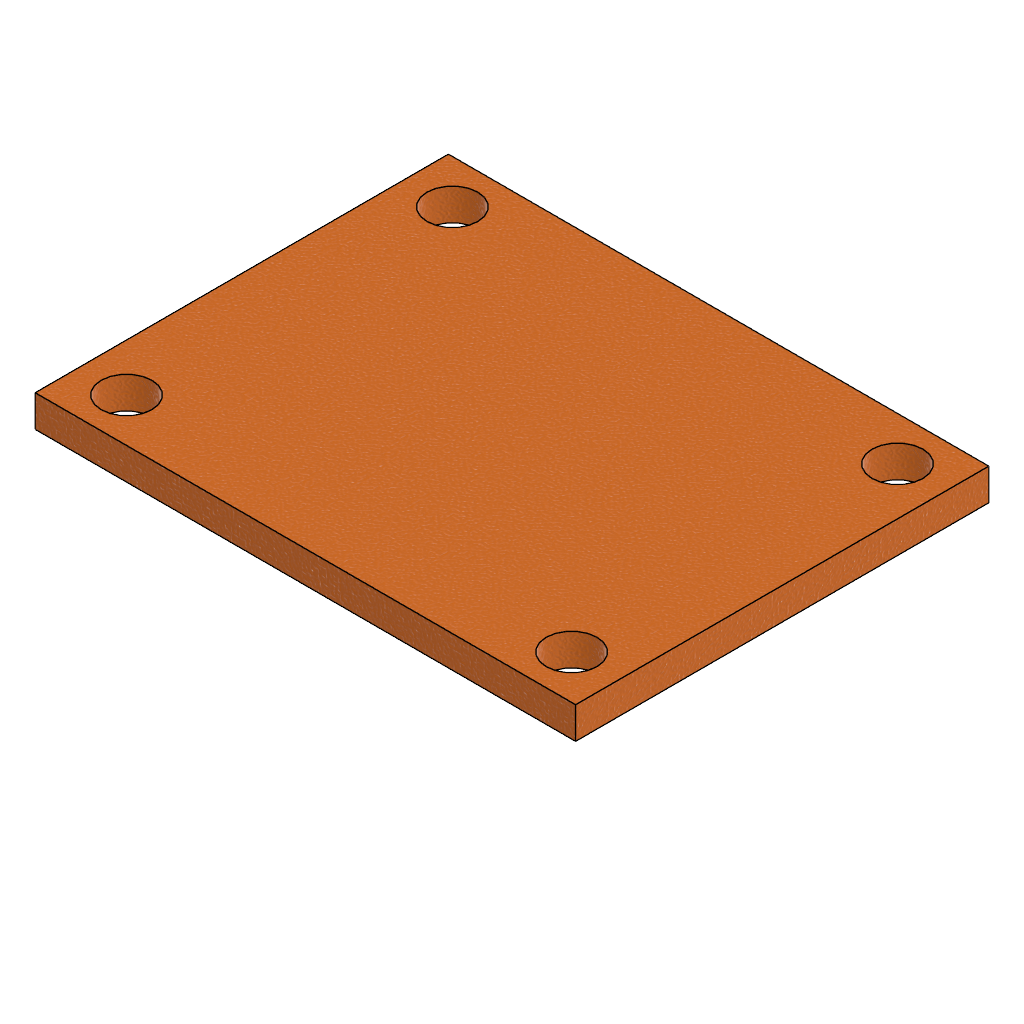
00-09 Joystick mount (Autodesk Fusion 360 design; units mm, degrees)
part number: 2026-11-09-11-43-06-006
Autodesk Fusion 360 part; units mm, degrees
sketch "Sketch1" plane through (0, 0, 0) normal (0, 0, 1) x (1, 0, 0)
  line L0 (0, 0) -> (34, 0)
  line L1 (34, 0) -> (34, 26)
  line L2 (34, 26) -> (0, 26)
  line L3 (0, 26) -> (0, 0)
  circle A0 centre (31, 2.75) radius 1.6
  circle A1 centre (31, 23.25) radius 1.6
  circle A2 centre (3, 23.25) radius 1.6
  circle A3 centre (3, 2.75) radius 1.6
  dimension "d1" = 34
  dimension "d2" = 26
  dimension "d3" = 20.5
  dimension "d4" = 3.2
  dimension "d5" = 2.75
  dimension "d6" = 28
  dimension "d7" = 3
  constraint horizontal L0
  constraint vertical L1
  constraint horizontal L2
  constraint vertical L3
  constraint coincident L0.start L3.end
  constraint equal A0 A1
  constraint equal A0 A3
  constraint equal A2 A3
  constraint horizontal A0.centre A3.centre
  constraint horizontal A1.centre A2.centre
  constraint vertical A0.centre A1.centre
  constraint vertical A2.centre A3.centre
  measures "d1" distance of L0.start L0.end
  measures "d2" distance of L0.end L1.end
  measures "d3" distance of A0.centre A1.centre
  measures "d4" diameter of A0
  measures "d5" distance of L0 A0.centre
  measures "d6" distance of A0.centre A3.centre
  measures "d7" distance of L1 A0.centre
extrude "Extrude1" add sketch "Sketch1" along normal blind 2
sketch "Sketch2" plane through (0, 0, 0) normal (0, 0, -1) x (1, 0, 0)
  circle A0 centre (3, -2.75) radius 1.6
  circle A1 centre (31, -2.75) radius 1.6
  circle A2 centre (3, -23.25) radius 1.6
  circle A3 centre (31, -23.25) radius 1.6
  line L0 (0, 0) -> (0, -26)
  line L1 (0, -26) -> (34, -26)
  line L2 (34, -26) -> (34, 0)
  line L3 (34, 0) -> (0, 0)
  circle A4 centre (17, -13) radius 3.5
  dimension "d10" = 7
  dimension "d11" = 13
  dimension "d12" = 17
  measures "d10" diameter of A4
  measures "d11" distance of L3 A4.centre
  measures "d12" distance of L0 A4.centre
extrude "Extrude2" add sketch "Sketch2" along normal blind 7 contours A4
